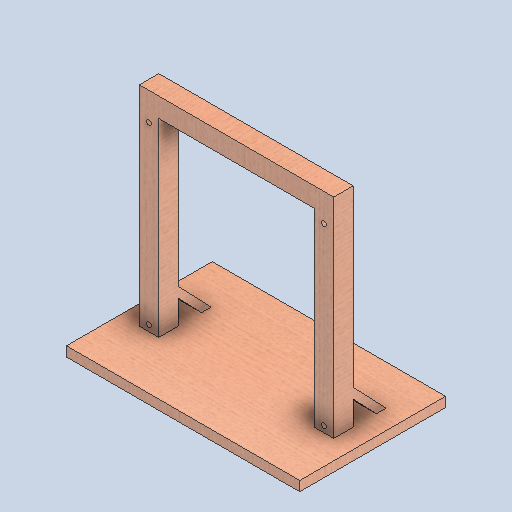
# Autodesk Inventor part: suporte
Saved by Autodesk Inventor 2026 (Build 300175000, 175)
## iProperties
Created: 2025-04-24
Part Number: suporte
Material: Wood (Walnut)
Document SubType Name: Modeling
Designer: dawac
Density: 0.55 g/cm^3
Appearance: Walnut - Natural Polished
Mass: 2668.67 g
Surface Area: 5241.55 cm^2
Volume: 4852.13 cm^3
Author: dawac
Autodesk Inventor part; units mm, degrees
ref_plane "YZ Plane" through (0, 0, 0) normal (1, 0, 0) x (0, 1, 0)
ref_plane "XZ Plane" through (0, 0, 0) normal (0, 1, 0) x (-1, 0, 0)
ref_plane "XY Plane" through (0, 0, 0) normal (0, 0, 1) x (1, 0, 0)
sketch "Sketch1" plane through (0, 0, 0) normal (0, 0, 1) x (1, 0, 0)
  line L0 (0, 0) -> (40, 0)
  line L1 (40, 0) -> (40, 430)
  line L2 (40, 430) -> (0, 430)
  line L3 (0, 430) -> (0, 0)
  circle A0 centre (20, 12.6) radius 5
  circle A1 centre (20, 372.6) radius 5
  line L4 (40, 430) -> (360, 430)
  line L5 (360, 430) -> (360, 390)
  line L6 (360, 390) -> (40, 390)
  line L7 (40, 390) -> (40, 430)
  line L8 (360, 430) -> (400, 430)
  line L9 (400, 430) -> (400, 0)
  line L10 (400, 0) -> (360, 0)
  line L11 (360, 0) -> (360, 430)
  circle A2 centre (380, 372.6) radius 5
  circle A3 centre (380, 12.6) radius 5
  point P0 (40, 390)
  dimension "d0" = 430
  dimension "d1" = 40
  dimension "d2" = 10
  dimension "d3" = 12.6
  dimension "d4" = 10
  dimension "d5" = 360
  dimension "d6" = 20
  dimension "d7" = 20
  dimension "d10" = 320
  dimension "d11" = 40
  dimension "d12" = 430
  dimension "d13" = 40
  dimension "d14" = 10
  dimension "d15" = 10
  dimension "d16" = 12.6
  dimension "d17" = 20
  dimension "d18" = 360
  dimension "d19" = 20
  constraints: 24 end point, 6 parallel, 4 centre point, 3 horizontal, 3 perpendicular
  measures "d0" distance of L0.end L1.end
  measures "d1" distance of L0.start L0.end
  measures "d2" diameter of A0
  measures "d3" vertical distance of A0.centre L0.start
  measures "d4" diameter of A1
  measures "d5" distance of A0.centre A1.centre
  measures "d6" horizontal distance of L0.start A0.centre
  measures "d7" distance from line of L3 A1.centre
  measures "d10" distance of L5.end L6.end
  measures "d11" distance of L4.end L5.end
  measures "d12" distance of L8.end L9.end
  measures "d13" distance of L4.end L8.end
  measures "d14" diameter of A2
  measures "d15" diameter of A3
  measures "d16" distance from line of L10 A3.centre
  measures "d17" horizontal distance of L9.end A3.centre
  measures "d18" distance of A2.centre A3.centre
  measures "d19" distance from line of L9 A2.centre
extrude "Extrusion1" add sketch "Sketch1" along normal blind 40
sketch "Sketch2" plane through (400, 0, 0) normal (1, 0, 0) x (0, 0, -1)
  line L0 (0, 0) -> (0, 390) projected
  line L1 (0, 50) -> (47.9055, 0)
  line L2 (47.9055, 0) -> (67.9055, 0)
  line L3 (67.9055, 0) -> (0, 70.8744)
  line L4 (0, 50) -> (0, 70.8744)
  dimension "d20" = 50
  dimension "d21" = 50
  dimension "d22" = 20
  dimension "d23" = 70.8744
  constraints: 8 end point, 2 perpendicular, 2 point on line, 1 parallel
  measures "d20" distance of L0.start L1.start
  measures "d21" vertical distance of L1.start L1.end
  measures "d22" distance of L2.end L1.end
  measures "d23" vertical distance of L3.end L2.end
extrude "Extrusion2" add sketch "Sketch2" against normal blind 40
sketch "Sketch4" plane through (0, 0, 0) normal (-1, 0, 0) x (0, 0, 1)
  line L0 (0, 50) -> (-47.9055, 0) projected
  line L1 (-47.9055, 0) -> (0, 50)
  line L2 (0, 50) -> (0, 70.619)
  line L3 (0, 0) -> (0, 390) projected
  line L4 (0, 70.8744) -> (-67.9055, 0) projected
  line L5 (-67.9055, 0) -> (-47.9055, 0)
  constraints: 6 end point, 1 collinear, 1 perpendicular, 1 point on line
extrude "Extrusion3" add sketch "Sketch4" against normal blind 40
sketch "Sketch5" plane through (360, 0, 0) normal (0, -1, 0) x (1, 0, 0)
  line L0 (80, -150) -> (-400, -150)
  line L1 (-400, -150) -> (-400, 150)
  line L2 (-400, 150) -> (80, 150)
  line L3 (80, 150) -> (80, -150)
  line L4 (40, 0) -> (40, 40) projected
  point P0 (-360, 0)
  dimension "d28" = 480
  dimension "d29" = 300
  dimension "d30" = 40
  dimension "d32" = 150
  constraints: 8 end point, 2 parallel, 1 horizontal, 1 perpendicular
  measures "d28" distance of L1.end L2.end
  measures "d29" distance of L2.end L0.start
  measures "d30" distance from line of point (-360, 0) L1
  measures "d32" distance from line of L2 point (-360, 0)
extrude "Extrusion4" add sketch "Sketch5" along normal blind 20
equation "\"d12\" = d0"
equation "\"d13\" = d1"
equation "\"d16\" = d3"
equation "\"d17\" = d6"
equation "\"d18\" = d5"
equation "\"d19\" = d7"
equation "\"d21\" = d20"
body "Solid1"
